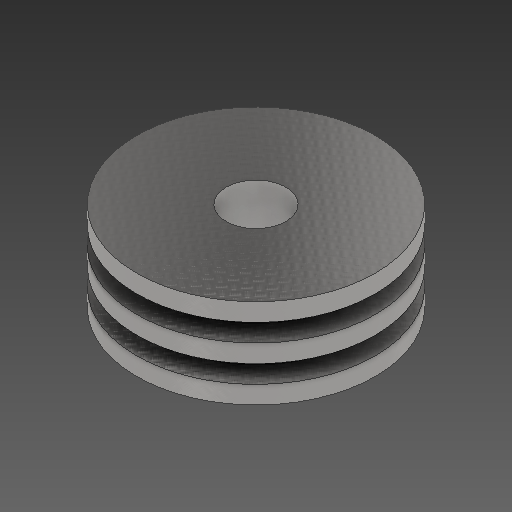
# Autodesk Inventor part: Pulley-Friday21
Saved by Autodesk Inventor 2026.1 (Build 301233020, 233B)
## iProperties
Created: 2026-08-21
Part Number: Pulley-Friday21
Material: Generic
Document SubType Name: Modeling
Designer: YmCris
Density: 1 g/cm^3
Appearance: Default
Author: YmCris
Autodesk Inventor part; units mm, degrees
ref_plane "YZ Plane" through (0, 0, 0) normal (1, 0, 0) x (0, 1, 0)
ref_plane "XZ Plane" through (0, 0, 0) normal (0, 1, 0) x (-1, 0, 0)
ref_plane "XY Plane" through (0, 0, 0) normal (0, 0, 1) x (1, 0, 0)
sketch "Sketch1" plane through (0, 0, 0) normal (0, 0, 1) x (1, 0, 0)
  line L0 (0, 0) -> (100, 0)
  line L1 (100, 0) -> (100, 15)
  line L2 (100, 15) -> (80, 15)
  line L3 (80, 15) -> (80, 30)
  line L4 (80, 30) -> (100, 30)
  line L5 (100, 30) -> (100, 45)
  line L6 (100, 45) -> (80, 45)
  line L7 (80, 45) -> (80, 60)
  line L8 (80, 60) -> (100, 60)
  line L9 (100, 60) -> (100, 75)
  line L10 (100, 75) -> (0, 75)
  line L11 (0, 75) -> (0, 0)
  dimension "d0" = 100
  dimension "d1" = 15
  dimension "d2" = 20
  dimension "d3" = 15
  dimension "d4" = 20
  dimension "d5" = 15
  dimension "d6" = 20
  dimension "d7" = 15
  dimension "d8" = 20
  dimension "d9" = 15
  constraints: 24 end point, 6 point on line, 4 perpendicular, 2 horizontal
  measures "d0" distance of L0.start L0.end
  measures "d1" distance of L0.end L1.end
  measures "d2" distance of L1.end L2.end
  measures "d3" distance of L2.end L3.end
  measures "d4" distance of L3.end L4.end
  measures "d5" distance of L4.end L5.end
  measures "d6" distance of L5.end L6.end
  measures "d7" distance of L6.end L7.end
  measures "d8" distance of L7.end L8.end
  measures "d9" distance of L8.end L9.end
revolve "Revolution1" add sketch "Sketch1" angle 360 about axis through (0, 75, 0) along (0, -1, 0)
sketch "Sketch2" plane through (0, 75, 0) normal (0, 1, 0) x (1, 0, 0)
  circle A0 centre (0, 0) radius 25
  dimension "d11" = 50
  constraints: 1 centre point, 1 coincident
  measures "d11" diameter of A0
extrude "Extrusion1" cut sketch "Sketch2" against normal blind 78.75
body "Solid1"
